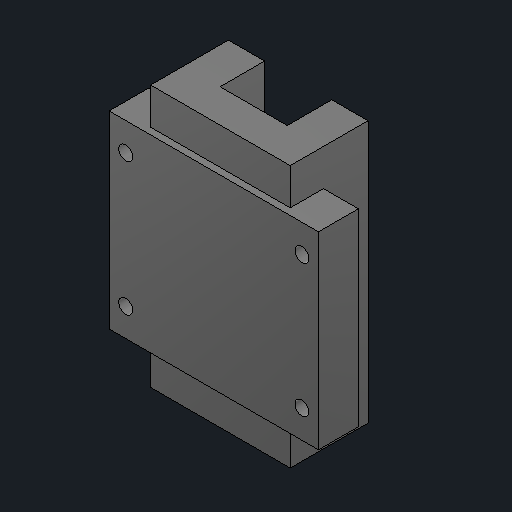
# Autodesk Inventor part: SBI20FL
Saved by Autodesk Inventor 2027.1 (Build 311270010, 270A)
## iProperties
Created: 2026-11-14
Part Number: SBI20FL
Material: Stainless Steel, 440C
Description: SBC flange carriage mounting envelope
Document SubType Name: Modeling
Designer: queezz
Density: 7.75 g/cm^3
Appearance: Smooth - Black
Author: queezz
Autodesk Inventor part; units mm, degrees
ref_plane "Work Plane1" through (0, 0, 18) normal (0, 0, 1) x (1, 0, 0)
sketch "Flange plan, 63 x 79.8" plane through (0, 0, 18) normal (0, 0, 1) x (1, 0, 0)
  line L0 (-31.5, -39.9) -> (31.5, -39.9)
  line L1 (31.5, -39.9) -> (31.5, 39.9)
  line L2 (31.5, 39.9) -> (-31.5, 39.9)
  line L3 (-31.5, 39.9) -> (-31.5, -39.9)
  constraints: 8 end point, 2 parallel, 1 horizontal, 1 perpendicular
extrude "Flange envelope" add sketch "Flange plan, 63 x 79.8" along normal blind 12
ref_plane "Work Plane2" through (0, 0, 4.6) normal (0, 0, 1) x (1, 0, 0)
sketch "Guide body and rail opening" plane through (0, 0, 4.6) normal (0, 0, 1) x (1, 0, 0)
  line L0 (-21, -39.9) -> (-10.1, -39.9)
  line L1 (-10.1, -39.9) -> (-10.1, 39.9)
  line L2 (-10.1, 39.9) -> (-21, 39.9)
  line L3 (-21, 39.9) -> (-21, -39.9)
  line L4 (10.1, -39.9) -> (21, -39.9)
  line L5 (21, -39.9) -> (21, 39.9)
  line L6 (21, 39.9) -> (10.1, 39.9)
  line L7 (10.1, 39.9) -> (10.1, -39.9)
  constraints: 16 end point, 4 parallel, 2 horizontal, 2 perpendicular
extrude "Guide body sides" add sketch "Guide body and rail opening" along normal blind 13.4
ref_plane "Work Plane3" through (0, 0, 30) normal (0, 0, 1) x (1, 0, 0)
sketch "M5 mounting pattern, 53 x 40" plane through (0, 0, 30) normal (0, 0, 1) x (1, 0, 0)
  circle A0 centre (-26.5, -20) radius 2.1
  circle A1 centre (-26.5, 20) radius 2.1
  circle A2 centre (26.5, -20) radius 2.1
  circle A3 centre (26.5, 20) radius 2.1
  constraints: 4 centre point
extrude "M5 mounting hole envelopes" cut sketch "M5 mounting pattern, 53 x 40" against normal blind 12
sketch "Sketch4" plane through (0, 0, 0) normal (0, 0, 1) x (1, 0, 0)
  line L0 (-34, -41) -> (34, -41)
  line L1 (34, -41) -> (34, -39.4)
  line L2 (34, -39.4) -> (-34, -39.4)
  line L3 (-34, -39.4) -> (-34, -41)
  line L4 (-34, 39.4) -> (34, 39.4)
  line L5 (34, 39.4) -> (34, 41)
  line L6 (34, 41) -> (-34, 41)
  line L7 (-34, 41) -> (-34, 39.4)
  constraints: 16 end point
extrude "Trim end caps to catalogue overall length" cut sketch "Sketch4" along normal blind 32
ref_plane "Work Plane4" through (0, 0, 18) normal (0, 0, 1) x (1, 0, 0)
sketch "Sketch5" plane through (0, 0, 18) normal (0, 0, 1) x (1, 0, 0)
  line L0 (-34, -41) -> (-21, -41)
  line L1 (-21, -41) -> (-21, -28.4)
  line L2 (-21, -28.4) -> (-34, -28.4)
  line L3 (-34, -28.4) -> (-34, -41)
  line L4 (-34, 28.4) -> (-21, 28.4)
  line L5 (-21, 28.4) -> (-21, 41)
  line L6 (-21, 41) -> (-34, 41)
  line L7 (-34, 41) -> (-34, 28.4)
  line L8 (21, -41) -> (34, -41)
  line L9 (34, -41) -> (34, -28.4)
  line L10 (34, -28.4) -> (21, -28.4)
  line L11 (21, -28.4) -> (21, -41)
  line L12 (21, 28.4) -> (34, 28.4)
  line L13 (34, 28.4) -> (34, 41)
  line L14 (34, 41) -> (21, 41)
  line L15 (21, 41) -> (21, 28.4)
  constraints: 32 end point
extrude "End cap sides below mounting flange" cut sketch "Sketch5" along normal blind 13
ref_plane "Work Plane5" through (0, 0, 28) normal (0, 0, 1) x (1, 0, 0)
sketch "Sketch6" plane through (0, 0, 28) normal (0, 0, 1) x (1, 0, 0)
  line L0 (-34, -41) -> (34, -41)
  line L1 (34, -41) -> (34, -28.4)
  line L2 (34, -28.4) -> (-34, -28.4)
  line L3 (-34, -28.4) -> (-34, -41)
  line L4 (-34, 28.4) -> (34, 28.4)
  line L5 (34, 28.4) -> (34, 41)
  line L6 (34, 41) -> (-34, 41)
  line L7 (-34, 41) -> (-34, 28.4)
  constraints: 16 end point
extrude "Recess end caps below steel mounting face" cut sketch "Sketch6" along normal blind 3
body "Solid1"
